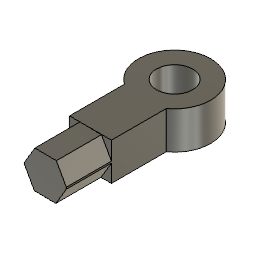
assemble22 (Autodesk Fusion 360 archive; units mm, degrees)
design "eyeend"
part number: 2026-08-27-14-23-14-280
Autodesk Fusion 360 part; units mm, degrees
sketch "Sketch1" plane through (0, 0, 0) normal (0, 0, 1) x (1, 0, 0)
  circle A0 centre (0, 0) radius 24
  circle A1 centre (0, 0) radius 7
  line L0 (0, 0) -> (0, -86)
  line L1 (0, -86) -> (14, -86)
  line L2 (14, -86) -> (-14, -86)
  line L3 (-14, -86) -> (-14, -19.4833)
  line L4 (-14, -19.4833) -> (14, -19.4833)
  line L5 (14, -19.4833) -> (14, -86)
  dimension "d1" = 48
  dimension "d2" = 14
  dimension "d3" = 86
  dimension "d4" = 14
  dimension "d5" = 28
  constraint coincident A0.centre A1.centre
  constraint concentric A0 A1
  constraint vertical L0
  constraint perpendicular L0 L1
  constraint horizontal L2
  constraint vertical L3
  constraint horizontal L4
  constraint vertical L5
  measures "d1" diameter of A0
  measures "d2" diameter of A1
  measures "d3" distance of A0.centre L0.end
  measures "d4" distance of L0.end L1.end
  measures "d5" distance of L1.end L2.end
extrude "Extrude1" add sketch "Sketch1" along normal blind 25
sketch "Sketch2" plane through (0, -86, 0) normal (0, -1, 0) x (1, 0, 0)
  line L0 (-14, 0) -> (14, 0)
  line L1 (14, 0) -> (14, 25)
  line L2 (14, 25) -> (-14, 25)
  line L3 (-14, 25) -> (-14, 0)
  line L4 (0, 0) -> (0, 0.0918)
  line L5 (-14, 12.5) -> (-14, 12.1069)
  line L6 (7, 0) -> (14.3253, 12.3122)
  line L7 (14.3253, 12.3122) -> (7.3253, 24.8122)
  line L8 (7.3253, 24.8122) -> (-7, 25)
  line L9 (-7, 25) -> (-14.3253, 12.6878)
  line L10 (-14.3253, 12.6878) -> (-7.3253, 0.1878)
  line L11 (-7.3253, 0.1878) -> (7, 0)
  point P0 (0, 12.5)
  dimension "d8" = 14
  dimension "d9" = 12.5
  constraint vertical L4
  constraint vertical L5
  constraint coincident L0 L6.start
  constraint coincident L11 L4.end
  constraint coincident L10 L5.end
  measures "d8" distance of L0.start L4.start
  measures "d9" distance of L0.start L5.start
extrude "Extrude2" cut sketch "Sketch2" against normal blind 30 contours L0 L3 L4 L10 L11 | L0 L1 L6 | L2 L3 L9 | L1 L2 L7 L8
sketch "Sketch3" plane through (0, 0, 25) normal (0, 0, 1) x (-1, 0, 0)
  line L0 (7, 56) -> (-14, 56)
  line L1 (-14, 56) -> (-14, 19.4936)
  arc A0 (-14, 19.4936) -> (14, 19.4936) centre (0, 0) ccw
  line L2 (14, 19.4936) -> (14, 56)
  line L3 (14, 56) -> (7, 56)
  circle A1 centre (0, 0) radius 7
hole "Hole1" at (0, 0, 25) direction (0, 0, -1) diameter 24 depth 90 tip angle 118

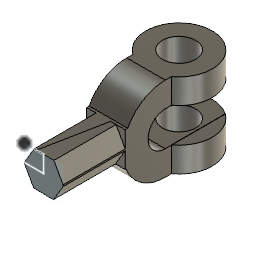
design "fork end"
part number: 2026-08-27-13-21-43-674
Autodesk Fusion 360 part; units mm, degrees
sketch "Sketch1" plane through (0, 0, 0) normal (1, 0, 0) x (0, 1, 0)
  arc A0 (0, 12.5) -> (0, -12.5) centre (0, 0) ccw
  line L0 (-30.0003, 0) -> (-30.5, 0)
  line L1 (-27.1664, 13.8649) -> (-29.9973, 14.0055)
  line L2 (-74, 13.9829) -> (-30, 13.9829)
  line L3 (-30.0011, -10.9945) -> (-74, -10.9945)
  line L4 (-74, -10.9945) -> (-74, 13.9829)
  arc A1 (0, 30.5) -> (-27.1664, 13.8649) centre (0, 0) ccw
  arc A2 (-28.4494, -10.9945) -> (0, -30.5) centre (0, 0) ccw
  line L5 (-27.1664, 13.8649) -> (-74, 13.9829)
  line L6 (-30.0011, -10.9945) -> (-28.4494, -10.9945)
  line L7 (0, 30.5) -> (48, 30.5)
  line L8 (0, 12.5) -> (48, 12.5)
  line L9 (0, -12.5) -> (48, -12.5)
  line L10 (48, -12.5) -> (48, -30.5)
  line L11 (48, -30.5) -> (0, -30.5)
  line L12 (48, 30.5) -> (48, 12.5)
  dimension "d1" = 25
  dimension "d9" = 25
  dimension "d29" = 18
  dimension "d30" = 18
  dimension "d31" = 48
  dimension "d32" = 48
  dimension "d33" = 48
  dimension "d34" = 18
  constraint coincident A0.centre A1.centre
  constraint horizontal L0
  constraint concentric A0 A1
  constraint tangent A0 L1
  constraint horizontal L2
  constraint horizontal L3
  constraint vertical L4
  constraint concentric A1 A2
  constraint coincident L3 A2.start
  constraint horizontal L7
  constraint tangent A0 L8
  constraint horizontal L9
  constraint vertical L10
  constraint horizontal L11
  constraint perpendicular L8 L12
  measures "d1" diameter of A0
  measures "d9" distance of L1.end L3.start
  measures "d29" distance of A0 A1
  measures "d30" distance of A0 A2
  measures "d31" distance of A1.start L7.end
  measures "d32" distance of A0.start L8.end
  measures "d33" distance of A0.end L9.end
  measures "d34" distance of A0.end A2.end
extrude "Extrude1" add sketch "Sketch1" along normal blind 28
sketch "Sketch8" plane through (0, 0, 30.5) normal (0, 0, 1) x (-1, 0, 0)
  line L0 (0, -48) -> (0, 0)
  line L1 (0, 0) -> (-28, 0)
  line L2 (-28, 0) -> (-28, -48)
  line L3 (-28, -48) -> (0, -48)
  line L4 (0, -48) -> (-14, -48)
  line L5 (-14, -48) -> (-14, -24)
  line L6 (-14, -24) -> (0, -24)
  line L7 (0, -24) -> (0, -48)
  circle A0 centre (-14, -24) radius 24
  circle A1 centre (-14, -24) radius 12
  dimension "d37" = 14
  dimension "d38" = 24
  dimension "d39" = 48
  dimension "d40" = 24
  constraint horizontal L4
  constraint vertical L5
  constraint horizontal L6
  constraint vertical L7
  constraint coincident L0.start L3.end
  constraint coincident L5.end L6.start
  constraint concentric A0 A1
  measures "d37" distance of L0.start L4.end
  measures "d38" distance of L0.start L6.end
  measures "d39" diameter of A0
  measures "d40" diameter of A1
extrude "Extrude7" add sketch "Sketch8" against normal blind 61 contours L0 L7 A0 | L2 A0
sketch "Sketch9" plane through (0, 0, 30.5) normal (0, 0, 1) x (-1, 0, 0)
  line L0 (0, -4.5064) -> (0, 0)
  line L1 (0, 0) -> (-28, 0)
  line L2 (-28, 0) -> (-28, -4.5064)
  arc A0 (-28, -4.5064) -> (-28, -43.4936) centre (-14, -24) ccw
  line L3 (-28, -43.4936) -> (-28, -48)
  line L4 (-28, -48) -> (0, -48)
  line L5 (0, -48) -> (0, -43.4936)
  arc A1 (0, -43.4936) -> (0, -4.5064) centre (-14, -24) ccw
  circle A2 centre (-14, -24) radius 24
  constraint concentric A0 A2
extrude "Extrude8" cut sketch "Sketch9" against normal blind 135 contours L4 L5 A2 | L3 L4 A2
sketch "Sketch10" plane through (28, 0, 0) normal (1, 0, 0) x (0, 1, 0)
  line L0 (4.5064, 12.5) -> (4.5064, 30.5)
  line L1 (4.5064, 30.5) -> (0, 30.5)
  arc A0 (0, 30.5) -> (-27.1664, 13.8649) centre (0, 0) ccw
  line L2 (-27.1664, 13.8649) -> (-74, 13.9829)
  line L3 (-74, 13.9829) -> (-74, -10.9945)
  line L4 (-74, -10.9945) -> (-28.4494, -10.9945)
  arc A1 (-28.4494, -10.9945) -> (0, -30.5) centre (0, 0) ccw
  line L5 (0, -30.5) -> (4.5064, -30.5)
  line L6 (4.5064, -30.5) -> (4.5064, -12.5)
  line L7 (4.5064, -12.5) -> (0, -12.5)
  arc A2 (0, 12.5) -> (0, -12.5) centre (0, 0) ccw
  line L8 (0, 12.5) -> (4.5064, 12.5)
  line L9 (4.5064, 12.5) -> (43.496, 12.5)
  line L10 (43.496, 12.5) -> (43.496, -12.3128)
  line L11 (43.496, -12.3128) -> (4.5064, -12.3128)
  line L12 (4.5064, -12.3128) -> (4.5064, 12.5)
  constraint horizontal L9
  constraint vertical L10
  constraint horizontal L11
  constraint vertical L12
  constraint coincident L0.start L8.end
extrude "Extrude9" cut sketch "Sketch10" along normal blind -155 and the other way blind -20 contours L9 L10 L11 L12
hole "Hole1" at (14, 24, 30.5) direction (0, 0, -1) diameter 24 depth 90 tip angle 118
sketch "Sketch11" plane through (0, -74, 0) normal (0, -1, 0) x (1, 0, 0)
  line L0 (0, 13.9829) -> (0, -10.9945)
  line L1 (0, -10.9945) -> (28, -10.9945)
  line L2 (28, -10.9945) -> (28, 13.9829)
  line L3 (28, 13.9829) -> (0, 13.9829)
  line L4 (0, 13.9829) -> (14, 13.9829)
  line L5 (14, 13.9829) -> (14, 1.9829)
  line L6 (14, 1.9829) -> (0, 1.9829)
  line L7 (0, 1.9829) -> (0, 13.9829)
  dimension "d52" = 14
  dimension "d53" = 12
  constraint horizontal L4
  constraint vertical L5
  constraint horizontal L6
  constraint vertical L7
  constraint coincident L0.start L3.end
  measures "d52" distance of L0.start L4.end
  measures "d53" distance of L0.start L6.end
sketch "Sketch2" plane through (0, -74, 0) normal (0, -1, 0) x (1, 0, 0)
  line L0 (0, 13.9829) -> (0, -10.9945)
  line L1 (0, -10.9945) -> (28, -10.9945)
  line L2 (28, -10.9945) -> (28, 13.9829)
  line L3 (28, 13.9829) -> (0, 13.9829)
  line L4 (0, -10.9945) -> (14, -10.9945)
  line L5 (14, -10.9945) -> (14, 1.5055)
  line L6 (14, 1.5055) -> (0, 1.5055)
  line L7 (0, 1.5055) -> (0, -10.9945)
  line L8 (21.0012, -10.9945) -> (28.3259, 1.3187)
  line L9 (28.3259, 1.3187) -> (21.3247, 13.8187)
  line L10 (21.3247, 13.8187) -> (6.9988, 14.0055)
  line L11 (6.9988, 14.0055) -> (-0.3259, 1.6923)
  line L12 (-0.3259, 1.6923) -> (6.6753, -10.8077)
  line L13 (6.6753, -10.8077) -> (21.0012, -10.9945)
  point P0 (14, 1.5055)
  dimension "d13" = 14
  dimension "d14" = 12.5
  constraint horizontal L4
  constraint vertical L5
  constraint horizontal L6
  constraint vertical L7
  constraint coincident L0.end L1.start
  constraint coincident L1 L8.start
  constraint coincident P0 L5.end
  measures "d13" distance of L0.end L4.end
  measures "d14" distance of L0.end L6.end
extrude "Extrude2" cut sketch "Sketch2" against normal blind 45 contours L0 L3 L11 | L2 L3 L9 L10 | L0 L1 L4 L5 L7 L12 L13 | L1 L2 L8

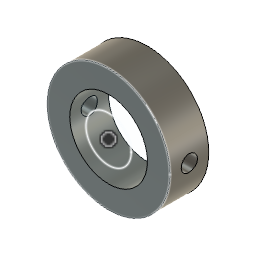
design "coller"
part number: 2026-09-03-13-16-02-014
Autodesk Fusion 360 part; units mm, degrees
sketch "Sketch1" plane through (0, 0, 0) normal (0, 1, 0) x (1, 0, 0)
  circle A0 centre (0, 0) radius 7
  circle A1 centre (0, 0) radius 19
  dimension "d1" = 14
  dimension "d2" = 38
  constraint coincident A0.centre A1.centre
  measures "d1" diameter of A0
  measures "d2" diameter of A1
extrude "Extrude1" add sketch "Sketch1" along normal blind 12 makes body 1
sketch "Sketch2" plane through (0, 0, 0) normal (1, 0, 0) x (0, 1, 0)
  line L0 (0, 19) -> (6, 19)
  line L1 (6, 19) -> (6, 0)
  line L2 (6, 0) -> (0, 0)
  line L3 (0, 0) -> (0, 19)
  circle A0 centre (6, 0) radius 2.5
  dimension "d5" = 6
  dimension "d6" = 5
  constraint horizontal L0
  constraint vertical L1
  constraint horizontal L2
  constraint vertical L3
  constraint coincident L1.end L2.start
  measures "d5" distance of L0.start L0.end
  measures "d6" diameter of A0
extrude "Extrude2" cut sketch "Sketch2" along normal blind 52 and the other way blind 63 contours L1 L2 A0 | L1 L2 A0 bodies 1
extrude "Extrude3" add sketch "Sketch1" along normal blind 12 separate body makes body 2
sketch "Sketch3" plane through (0, 0, 0) normal (1, 0, 0) x (0, 1, 0)
  circle A0 centre (6, 0) radius 2.5
  dimension "d13" = 5
  measures "d13" diameter of A0
extrude "Extrude4" cut sketch "Sketch3" along normal blind 39 and the other way blind 37 bodies 2
sketch "Sketch4" plane through (0, 0, 0) normal (0, 1, 0) x (1, 0, 0)
  circle A0 centre (0, 0) radius 12
  dimension "d18" = 24
  constraint coincident A0.centre origin
  measures "d18" diameter of A0
extrude "Extrude5" cut sketch "Sketch4" along normal blind 31 bodies 1 2

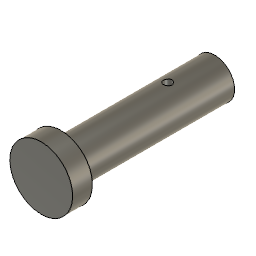
design "pin"
part number: 2026-08-27-13-46-03-875
Autodesk Fusion 360 part; units mm, degrees
sketch "Sketch1" plane through (0, 0, 0) normal (0, 1, 0) x (1, 0, 0)
  circle A0 centre (0, 0) radius 19
  circle A1 centre (0, 0) radius 7
  dimension "d1" = 38
  dimension "d2" = 14
  constraint coincident A0.centre A1.centre
  measures "d1" diameter of A0
  measures "d2" diameter of A1
extrude "Extrude1" add sketch "Sketch1" along normal blind 12 makes body 1
sketch "Sketch2" plane through (0, 0, 0) normal (0, -1, 0) x (1, 0, 0)
  circle A0 centre (0, 0) radius 7
  circle A1 centre (0, 0) radius 19
  circle A2 centre (0, 0) radius 12
  dimension "d5" = 24
  constraint coincident A0.centre A1.centre
  measures "d5" diameter of A2
sketch "Sketch3" plane through (0, 0, 0) normal (0, 0, 1) x (1, 0, 0)
  line L0 (12, -80) -> (12, -70)
  line L1 (12, -70) -> (0, -70)
  circle A0 centre (0, -70) radius 2.5
  dimension "d8" = 10
  dimension "d9" = 12
  dimension "d10" = 5
  constraint vertical L0
  constraint perpendicular L0 L1
  constraint coincident L1.end A0.centre
  measures "d8" distance of L0.start L0.end
  measures "d9" distance of L0.end L1.end
  measures "d10" diameter of A0
extrude "Extrude4" [suppressed]
extrude "Extrude5" add sketch "Sketch1" along normal blind 90 separate body contours A1 makes body 2
sketch "Sketch5" plane through (0, 0, 0) normal (0, 0, 1) x (1, 0, 0)
  line L0 (-7, 90) -> (0, 90)
  line L1 (0, 90) -> (0, 80)
  line L2 (0, 80) -> (-7, 80)
  line L3 (-7, 80) -> (-7, 90)
  circle A0 centre (0, 80) radius 2.5
  dimension "d25" = 7
  dimension "d26" = 10
  dimension "d27" = 5
  constraint horizontal L0
  constraint vertical L1
  constraint horizontal L2
  constraint vertical L3
  constraint coincident L1.end L2.start
  measures "d25" distance of L0.start L0.end
  measures "d26" distance of L0.start L2.end
  measures "d27" diameter of A0
extrude "Extrude7" cut sketch "Sketch5" along normal blind 30 and the other way blind 75 contours L1 L2 A0 | L1 L2 A0 bodies 2
sketch "Sketch6" plane through (0, 90, 0) normal (0, 1, 0) x (-1, 0, 0)
  circle A0 centre (0, 0) radius 7
  circle A1 centre (0, 0) radius 12
  dimension "d32" = 24
  constraint coincident A0.centre A1.centre
  measures "d32" diameter of A1
extrude "Extrude8" add sketch "Sketch6" along normal blind -78 and the other way blind -15 contours A0 | A1 bodies 1 2
sketch "Sketch7" plane through (0, 0, 0) normal (0, 0, 1) x (1, 0, 0)
  line L0 (-12, 12) -> (-12, 72)
  line L1 (-12, 72) -> (0, 72)
  line L2 (0, 72) -> (0, 76.5)
  line L3 (0, 76.5) -> (-12, 76.5)
  line L4 (-12, 76.5) -> (-12, 72)
  circle A0 centre (0, 76.5) radius 2.5
  dimension "d37" = 60
  dimension "d38" = 12
  dimension "d39" = 4.5
  dimension "d40" = 5
  constraint vertical L0
  constraint horizontal L1
  constraint vertical L2
  constraint horizontal L3
  constraint vertical L4
  constraint coincident L2.end L3.start
  measures "d37" distance of L0.start L0.end
  measures "d38" distance of L0.end L1.end
  measures "d39" distance of L0.end L3.end
  measures "d40" diameter of A0
extrude "Extrude9" cut sketch "Sketch7" along normal blind 100 and the other way blind 45 contours L2 L3 A0 | L2 L3 A0 bodies 1
sketch "Sketch4" plane through (0, 0, 0) normal (0, 0, 1) x (1, 0, 0)
  line L0 (7, 80) -> (0, 80)
  line L1 (0, 80) -> (0, 70)
  line L2 (0, 70) -> (7, 70)
  line L3 (7, 70) -> (7, 80)
  circle A0 centre (0, 70) radius 2.5
  dimension "d19" = 7
  dimension "d20" = 5
  constraint horizontal L0
  constraint vertical L1
  constraint horizontal L2
  constraint vertical L3
  constraint coincident L1.end L2.start
  measures "d19" distance of L0.start L0.end
  measures "d20" diameter of A0
extrude "Extrude6" [suppressed]

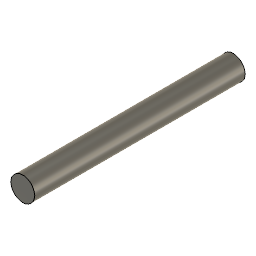
design "tapperpin"
part number: 2026-09-03-13-14-33-161
Autodesk Fusion 360 part; units mm, degrees
sketch "Sketch1" plane through (0, 0, 0) normal (0, 1, 0) x (1, 0, 0)
  circle A0 centre (0, 0) radius 2.5
  dimension "d1" = 5
  constraint coincident A0.centre origin
  measures "d1" diameter of A0
extrude "Extrude1" add sketch "Sketch1" along normal blind 44
